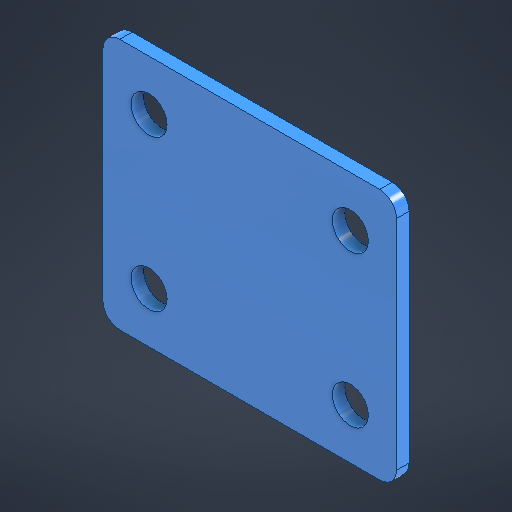
# Autodesk Inventor part: Linear Bearing Spacer
Saved by Autodesk Inventor 2027.1 (Build 311270010, 270A)
## iProperties
Created: 2026-10-08
Part Number: Linear Bearing Spacer
Material: Generic
Document SubType Name: Modeling
Designer: Ahmed
Density: 1 g/cm^3
Appearance: Cyan
Author: Ahmed
Autodesk Inventor part; units mm, degrees
ref_plane "YZ Plane" through (0, 0, 0) normal (1, 0, 0) x (0, 1, 0)
ref_plane "XZ Plane" through (0, 0, 0) normal (0, 1, 0) x (-1, 0, 0)
ref_plane "XY Plane" through (0, 0, 0) normal (0, 0, 1) x (1, 0, 0)
sketch "Sketch1" plane through (0, 0, 0) normal (0, 0, 1) x (1, 0, 0)
  line L0 (-15.5, 15) -> (15.5, 15)
  line L1 (17.5, 13) -> (17.5, -13)
  line L2 (15.5, -15) -> (-15.5, -15)
  line L3 (-17.5, -13) -> (-17.5, 13)
  line L4 (-17.5, 15) -> (17.5, -15) construction
  line L5 (17.5, 15) -> (-17.5, -15) construction
  line L6 (12, -9) -> (-12, -9)
  line L7 (-12, -9) -> (-12, 9)
  line L8 (-12, 9) -> (12, 9)
  line L9 (12, 9) -> (12, -9)
  line L10 (12, -9) -> (-12, 9) construction
  line L11 (-12, -9) -> (12, 9) construction
  circle A0 centre (-12, 9) radius 2.15
  circle A1 centre (12, 9) radius 2.15
  circle A2 centre (-12, -9) radius 2.15
  circle A3 centre (12, -9) radius 2.15
  arc A4 (-15.5, 15) -> (-17.5, 13) centre (-15.5, 13) ccw
  arc A5 (-17.5, -13) -> (-15.5, -15) centre (-15.5, -13) ccw
  arc A6 (15.5, -15) -> (17.5, -13) centre (15.5, -13) ccw
  arc A7 (17.5, 13) -> (15.5, 15) centre (15.5, 13) ccw
  point P0 (0, 0)
  dimension "d0" = 35
  dimension "d1" = 30
  dimension "d2" = 24
  dimension "d3" = 18
  dimension "d4" = 4.3
  dimension "d7" = 24
  dimension "d10" = 18
  dimension "d15" = 2
  constraints: 24 end point, 8 centre point, 8 point on circle, 8 point on line, 8 tangent, 4 midpoint, 4 parallel, 3 equal radius, 3 horizontal, 2 perpendicular, 1 coincident, 1 vertical, 6 other
  measures "d0" distance of L4.end L5.end
  measures "d1" distance of L5.start L4.end
  measures "d2" distance of L7.end L8.end
  measures "d3" distance of L6.end L7.end
  measures "d4" diameter of A0
  measures "d7" distance of A0.centre A1.centre
  measures "d10" distance of A0.centre A2.centre
  measures "d15" radius of A4
extrude "Extrusion1" add sketch "Sketch1" along normal blind 1.5 contours L0 A7 L1 A6 L2 A5 L3 A4 | A2 L7 A0 L8 A1 L9 A3 L6
equation "\"d7\" = d2"
equation "\"d10\" = d3"
body "Solid1"
